Autodesk Fusion 360 part; units mm, degrees
(part 9 of 9)
equation "d1308 = abs(mountCircle / ( 2 * sqrt(2) ))"
equation "d1309 = abs(-mountCircle / ( 2 * sqrt(2) ))"
equation "d1314 = -qFront - nutDepth"
equation "d1316 = abs(mountCircle / ( 2 * sqrt(2) ))"
equation "d1317 = abs(-mountCircle / ( 2 * sqrt(2) ))"
equation "d1318 = 2 * ( 7 mm ) / sqrt(3)"
equation "d1321 = abs(mountCircle / ( 2 * sqrt(2) ))"
equation "d1322 = abs(-mountCircle / ( 2 * sqrt(2) ))"
equation "d1329 = qRearEnd + capThickness + 0.5 mm - 45 mm"
equation "d1331 = supportCircle / 2"
equation "d1335 = qRearEnd + capThickness + 0.5 mm"
equation "d1337 = supportCircle / 2"
equation "d1341 = qRearEnd + capThickness"
equation "d1343 = supportCircle / 2"
equation "d1348 = qFront - capThickness - 0.5 mm"
equation "d1350 = supportCircle / 2"
equation "d1355 = qFront - capThickness - 4.5 mm"
equation "d1357 = supportCircle / 2"
equation "driverPort = 5 mm" comment "Clearance for bare3 mm hex-key shafts; bulky bit holders do not fit."
equation "accessPadWidth = 12 mm" comment "Reinforced access-port capsule width."
equation "accessPadExtra = 2 mm" comment "Local inward reinforcement beyond nominal side wall."
equation "d1369 = bodyWidth / 2"
equation "d1451 = abs(55 mm)"
equation "d1452 = abs(66.5 mm)"
equation "d1453 = abs(130 mm)"
equation "d1454 = abs(66.5 mm)"
equation "d1455 = abs(130 mm)"
equation "d1456 = abs(75 mm)"
equation "d1457 = abs(55 mm)"
equation "d1458 = abs(75 mm)"
equation "d1469 = abs(48 mm)"
equation "d1470 = abs(-35 mm)"
equation "d1471 = abs(130 mm)"
equation "d1472 = abs(-35 mm)"
equation "d1473 = abs(130 mm)"
equation "d1474 = abs(35 mm)"
equation "d1475 = abs(48 mm)"
equation "d1476 = abs(35 mm)"
equation "d1487 = bodyWidth / 2"
equation "d1489 = abs(( -1 ) * ( -bodyWidth / 2 + sqrt(2) * ( mountCircle / ( 2 * sqrt(2) ) ) ) + ( 0 ) * ( mountCircle / ( 2 * sqrt(2) ) ))"
equation "d1490 = abs(( 0 ) * ( -bodyWidth / 2 + sqrt(2) * ( mountCircle / ( 2 * sqrt(2) ) ) ) + ( 1 ) * ( mountCircle / ( 2 * sqrt(2) ) ))"
equation "d1493 = -( wall + accessPadExtra )"
equation "d1495 = abs(( -1 ) * ( -bodyWidth / 2 + sqrt(2) * ( mountCircle / ( 2 * sqrt(2) ) ) ) + ( 0 ) * ( -mountCircle / ( 2 * sqrt(2) ) ))"
equation "d1496 = abs(( 0 ) * ( -bodyWidth / 2 + sqrt(2) * ( mountCircle / ( 2 * sqrt(2) ) ) ) + ( 1 ) * ( -mountCircle / ( 2 * sqrt(2) ) ))"
equation "d1499 = -( wall + accessPadExtra )"
equation "d1501 = abs(( -1 ) * ( -bodyWidth / 2 + sqrt(2) * ( -mountCircle / ( 2 * sqrt(2) ) ) ) + ( 0 ) * ( -mountCircle / ( 2 * sqrt(2) ) ))"
equation "d1502 = abs(( 0 ) * ( -bodyWidth / 2 + sqrt(2) * ( -mountCircle / ( 2 * sqrt(2) ) ) ) + ( 1 ) * ( -mountCircle / ( 2 * sqrt(2) ) ))"
equation "d1505 = -( wall + accessPadExtra )"
equation "d1507 = abs(( -1 ) * ( -bodyWidth / 2 + sqrt(2) * ( -mountCircle / ( 2 * sqrt(2) ) ) ) + ( 0 ) * ( mountCircle / ( 2 * sqrt(2) ) ))"
equation "d1508 = abs(( 0 ) * ( -bodyWidth / 2 + sqrt(2) * ( -mountCircle / ( 2 * sqrt(2) ) ) ) + ( 1 ) * ( mountCircle / ( 2 * sqrt(2) ) ))"
equation "d1511 = -( wall + accessPadExtra )"
equation "d1515 = abs(mountCircle / ( 2 * sqrt(2) ))"
equation "d1516 = abs(mountCircle / ( 2 * sqrt(2) ))"
equation "d1517 = driverPort"
equation "d1518 = abs(-mountCircle / ( 2 * sqrt(2) ))"
equation "d1519 = abs(mountCircle / ( 2 * sqrt(2) ))"
equation "d1520 = driverPort"
equation "d1521 = abs(-mountCircle / ( 2 * sqrt(2) ))"
equation "d1522 = abs(-mountCircle / ( 2 * sqrt(2) ))"
equation "d1523 = driverPort"
equation "d1524 = abs(mountCircle / ( 2 * sqrt(2) ))"
equation "d1525 = abs(-mountCircle / ( 2 * sqrt(2) ))"
equation "d1526 = driverPort"
equation "d1527 = -( bodyLength )"
named bodies: "A Housing print", "B Moving Body print", "A Housing print (1)"
